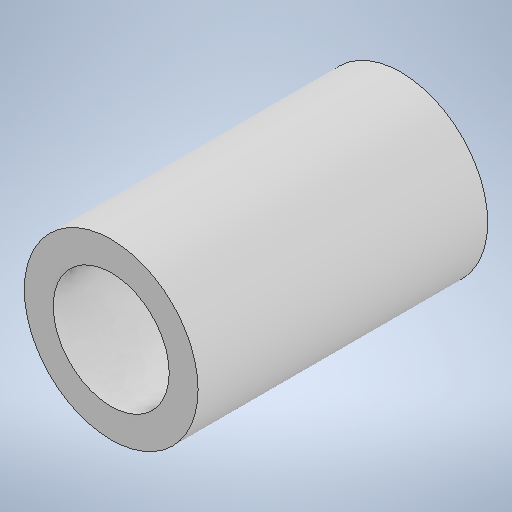
# Autodesk Inventor part: Gonzo femea
Saved by Autodesk Inventor 2025.1 (Build 291241020, 241B)
## iProperties
Created: 2024-11-19
Part Number: Gonzo femea
Material: Genérico
Document SubType Name: Modeling
Designer: Alecs
Density: 1 g/cm^3
Appearance: Padrão
Author: Alecs
Autodesk Inventor part; units mm, degrees
ref_plane "YZ Plane" through (0, 0, 0) normal (1, 0, 0) x (0, 1, 0)
ref_plane "XZ Plane" through (0, 0, 0) normal (0, 1, 0) x (-1, 0, 0)
ref_plane "XY Plane" through (0, 0, 0) normal (0, 0, 1) x (1, 0, 0)
sketch "Esboço1" plane through (0, 0, 0) normal (0, 0, 1) x (1, 0, 0)
  circle A0 centre (0, 0) radius 5.005
  circle A1 centre (0, 0) radius 7.5
  dimension "d0" = 15
  dimension "d1" = 10.01
  constraints: 2 centre point, 2 coincident
  measures "d0" diameter of A1
  measures "d1" diameter of A0
extrude "Extrusão1" add sketch "Esboço1" along normal blind 25
